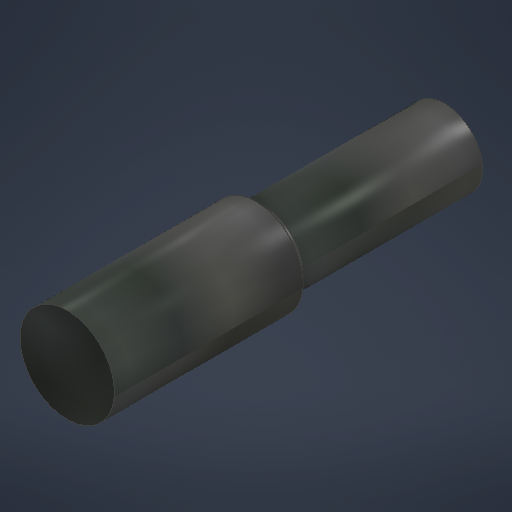
# Autodesk Inventor part: Pieza1
Saved by Autodesk Inventor 2026 (Build 300175050, 175E)
## iProperties
Created: 2026-11-04
Part Number: Pieza1
Material: Acero
Document SubType Name: Modeling
Designer: chaco
Density: 7.85 g/cm^3
Appearance: Placa
Author: chaco
Autodesk Inventor part; units mm, degrees
ref_plane "YZ Plane" through (0, 0, 0) normal (1, 0, 0) x (0, 1, 0)
ref_plane "XZ Plane" through (0, 0, 0) normal (0, 1, 0) x (-1, 0, 0)
ref_plane "XY Plane" through (0, 0, 0) normal (0, 0, 1) x (1, 0, 0)
sketch "Boceto2" plane through (0, 0, 0) normal (0, 1, 0) x (-1, 0, 0)
  line L0 (0, 0) -> (0.625, 0)
  line L1 (0.625, 0) -> (0.625, 2.5)
  line L2 (0.625, 2.5) -> (0, 2.5)
  line L3 (0, 2.5) -> (0, 0)
  line L4 (0, 0) -> (0.5, 0)
  line L5 (0.5, 0) -> (0.5, -2.5)
  line L6 (0.5, -2.5) -> (0, -2.5)
  line L7 (0, -2.5) -> (0, 0)
  dimension "d0" = 0.625
  dimension "d1" = 2.5
  dimension "d2" = 0.5
  dimension "d3" = 2.5
  constraints: 16 end point, 4 parallel, 2 horizontal, 2 perpendicular
  measures "d0" distance of L2.end L1.end
  measures "d1" distance of L1.end L0.end
  measures "d2" distance of L5.end L6.end
  measures "d3" distance of L4.end L5.end
revolve "Revolución1" add sketch "Boceto2" angle 360 about axis through (0, 0, 2.5) along (0, 0, -1)
fillet "Empalme1" radius 0.125 1 edges at (0.5, 0, 0)
